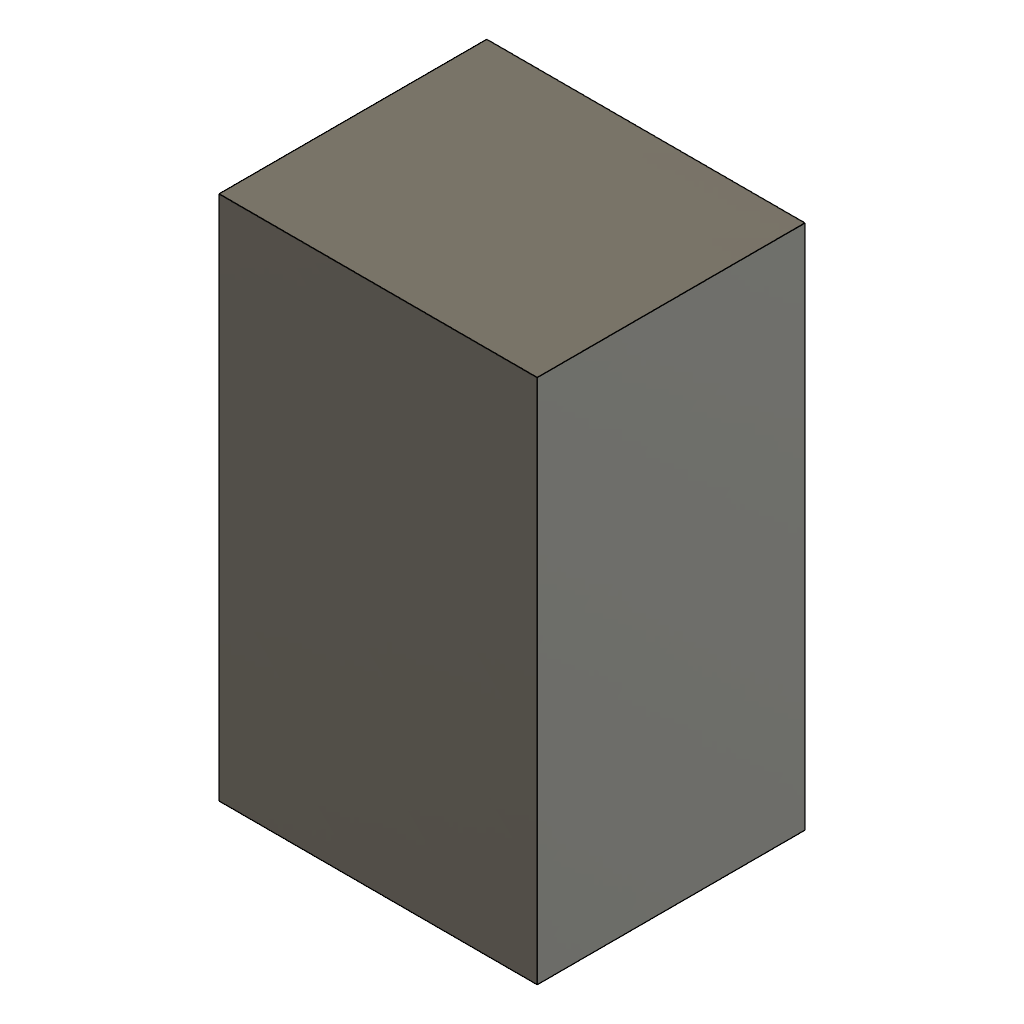
BaselineControl (Autodesk Fusion 360 design; units mm, degrees)
part number: 2026-11-25-21-25-09-490
Autodesk Fusion 360 part; units mm, degrees
sketch "Encoder Rectangle" plane through (0, 0, 0) normal (0, 0, 1) x (1, 0, 0)
  line L0 (0, 0) -> (16.4, 0)
  line L1 (16.4, 0) -> (16.4, 27.1)
  line L2 (16.4, 27.1) -> (0, 27.1)
  line L3 (0, 27.1) -> (0, 0)
  dimension "d4" = 16.4
  dimension "d5" = 27.1
  constraint horizontal L0
  constraint vertical L1
  constraint horizontal L2
  constraint vertical L3
  measures "d4" horizontal distance of L0.start L0.end
  measures "d5" vertical distance of L0.start L2.end
extrude "Encoder Extrusion" add sketch "Encoder Rectangle" along normal blind 13.8
equation "kitWidth = 16.4 mm"
equation "kitDepth = 27.1 mm"
equation "kitHeight = 13.8 mm"
equation "d4 = kitWidth"
equation "d5 = kitDepth"
equation "d6 = kitHeight"
named bodies: "Encoder Cuboid"
